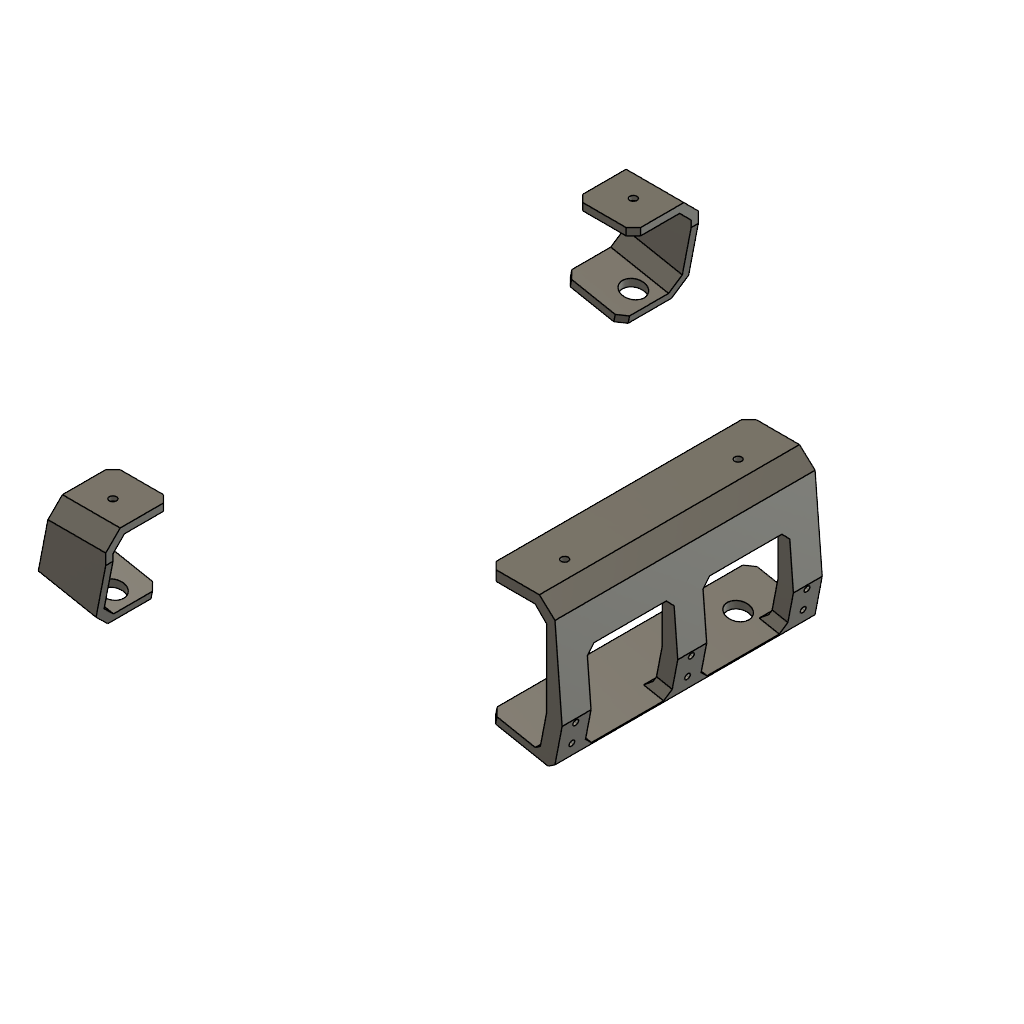
LaptopDeskMountMk2 (Autodesk Fusion 360 design; units mm, degrees)
part number: 2026-11-20-12-05-45-084
Autodesk Fusion 360 part; units mm, degrees
sketch "Sketch1" plane through (0, 0, 0) normal (0, 0, 1) x (1, 0, 0)
  line L0 (0, 0) -> (280, 0)
  line L1 (280, 0) -> (280, -127.8735)
  line L2 (0, 0) -> (280, -54.4265)
  line L3 (0, 0) -> (285.2407, 0) construction
  line L4 (0, 0) -> (50, 0)
  line L5 (50, 0) -> (90, 0)
  line L6 (50, 0) -> (50, -9.719)
  line L7 (90, 0) -> (90, -17.4942)
  line L8 (90, -17.4942) -> (82.3676, -56.7593)
  line L9 (50, -9.719) -> (42.3676, -48.9841)
  line L10 (42.3676, -48.9841) -> (82.3676, -56.7593)
  dimension "d1" = 280
  dimension "d2" = 11
  dimension "d3" = 50
  dimension "d4" = 40
  dimension "d5" = 40
  dimension "d6" = 40
  constraint coincident L0.start L2.start
  constraint horizontal L0
  constraint perpendicular L0 L1
  constraint horizontal L3
  constraint coincident L1 L2.end
  constraint parallel L3 L4
  constraint parallel L3 L5
  constraint coincident L2 L6.end
  constraint perpendicular L4 L6
  constraint coincident L2 L7.end
  constraint perpendicular L0 L7
  constraint perpendicular L2 L8
  constraint perpendicular L2 L9
  measures "d1" distance of L0.start L0.end
  measures "d2" angle of L2 L3
  measures "d3" distance of L0.start L4.end
  measures "d4" distance of L4.end L5.end
  measures "d5" distance of L7.end L8.end
  measures "d6" distance of L6.end L9.end
extrude "Extrude1" add sketch "Sketch1" along normal blind 5 contours L0 L2 L5 L6 L7 | L2 L8 L9 L10 makes body 1
sketch "Sketch2" plane through (0, 0, 0) normal (0, 1, 0) x (-1, 0, 0)
  line L0 (-90, 0) -> (-50, 0)
  line L1 (-50, 0) -> (-50, 5)
  line L2 (-50, 5) -> (-90, 5)
  line L3 (-90, 5) -> (-90, 0)
  line L4 (-90, 5) -> (-90, 45)
  line L5 (-90, 45) -> (-50, 45)
  line L6 (-50, 45) -> (-50, 5)
  line L7 (-50, 5) -> (-90, 5)
  line L8 (-90, 5) -> (-90, 45)
  line L9 (-90, 25) -> (-50, 25)
  circle A0 centre (-70, 25) radius 2.5
  dimension "d9" = 40
  dimension "d10" = 5
  constraint coincident L2.end L3.start
  constraint perpendicular L2 L4
  constraint horizontal L5
  constraint vertical L6
  constraint horizontal L7
  constraint vertical L8
  constraint coincident L1.end L2.start
  constraint midpoint L8 L9.start
  constraint midpoint L6 L9.end
  constraint midpoint L9 A0.centre
  measures "d9" distance of L2.end L4.end
  measures "d10" diameter of A0
extrude "Extrude2" add sketch "Sketch2" against normal blind 5 contours L2 L4 L6 L7 L8 L9 A0 | L4 L5 L6 L8 L9 A0 bodies 1
sketch "Sketch3" plane through (-7.6324, -39.2651, 0) normal (-0.190809, -0.981627, 0) x (0, 0, 1)
  line L0 (0, -50.9358) -> (0, -91.6845)
  line L1 (0, -91.6845) -> (5, -91.6845)
  line L2 (5, -91.6845) -> (5, -50.9358)
  line L3 (5, -50.9358) -> (0, -50.9358)
  line L4 (5, -50.9358) -> (45, -50.9358)
  line L5 (45, -50.9358) -> (5, -50.9358)
  line L6 (5, -50.9358) -> (5, -91.6845)
  line L7 (5, -91.6845) -> (45, -91.6845)
  line L8 (45, -91.6845) -> (45, -50.9358)
  dimension "d13" = 40
  constraint coincident L2.end L3.start
  constraint perpendicular L2 L4
  constraint horizontal L5
  constraint vertical L6
  constraint horizontal L7
  constraint vertical L8
  constraint coincident L1.end L2.start
  measures "d13" distance of L2.end L4.end
extrude "Extrude3" add sketch "Sketch3" along normal blind 5 bodies 1
sketch "Sketch4" plane through (0, -5, 0) normal (0, -1, 0) x (1, 0, 0)
  circle A0 centre (70, 25) radius 2.5
  line L0 (50, 5) -> (90, 5)
  line L1 (90, 5) -> (90, 45)
  line L2 (90, 45) -> (50, 45)
  line L3 (50, 45) -> (50, 5)
  circle A1 centre (70, 25) radius 7.5
  dimension "d16" = 15
  constraint concentric A0 A1
  measures "d16" diameter of A1
extrude "Extrude4" cut sketch "Sketch4" along normal blind 60 contours A0 | A1 bodies 1
hole "Hole1" at (70, -5, 25) direction (0, 1, 0) diameter 8 depth 1 tip angle 118 bodies 1
chamfer "Chamfer2" distance 8 angle 45 2 edges at (70, -5, 5) (62.3676, -52.8717, 5) tangent chain off on bodies 1
chamfer "Chamfer3" distance 10 angle 45 2 edges at (70, 0, 0) (61.4136, -57.7798, 0) tangent chain off on bodies 1
chamfer "Chamfer4" distance 5 angle 45 4 edges at (50, -2.5, 45) (90, -2.5, 45) (41.8906, -51.4382, 45) (81.8906, -59.2134, 45) tangent chain off on bodies 1
sketch "Sketch5" plane through (0, 0, 0) normal (0, 0, 1) x (1, 0, 0)
  line L0 (0, 0) -> (280, 0)
  line L1 (280, 0) -> (280, -128)
  line L2 (0, 0) -> (280, -54.4265)
  line L3 (0, 0) -> (285.2407, 0) construction
  line L4 (280, 0) -> (240, 0)
  line L5 (280, 0) -> (285, 0)
  line L6 (280, -54.4265) -> (280, -94.4265)
  line L7 (280, -94.4265) -> (240.7349, -86.7941)
  line L8 (280, -94.4265) -> (320, -94.4265) construction
  line L9 (240.7349, -86.7941) -> (239.7809, -91.7023)
  line L10 (239.7809, -91.7023) -> (285, -100.492)
  line L11 (285, -100.492) -> (285, 0)
  line L12 (240, 0) -> (240, -7)
  line L13 (240, -7) -> (280, -7)
  dimension "d19" = 280
  dimension "d20" = 128
  dimension "d21" = 11
  dimension "d22" = 40
  dimension "d23" = 5
  dimension "d24" = 40
  dimension "d25" = 169
  dimension "d26" = 40
  dimension "d27" = 5
  dimension "d28" = 7
  constraint coincident L0.start L2.start
  constraint horizontal L0
  constraint perpendicular L0 L1
  constraint horizontal L3
  constraint coincident L1 L2.end
  constraint perpendicular L1 L4
  constraint perpendicular L1 L5
  constraint parallel L1 L6
  constraint horizontal L8
  constraint perpendicular L7 L9
  constraint perpendicular L9 L10
  constraint perpendicular L5 L11
  constraint perpendicular L0 L12
  constraint coincident L1 L13.end
  constraint perpendicular L1 L13
  measures "d19" distance of L0.start L0.end
  measures "d20" distance of L0.end L1.end
  measures "d21" angle of L2 L3
  measures "d22" distance of L0.end L4.end
  measures "d23" distance of L0.end L5.end
  measures "d24" distance of L2.end L6.end
  measures "d25" angle of L7 L8
  measures "d26" distance of L6.end L7.end
  measures "d27" distance of L7.end L9.end
  measures "d28" distance of L4.end L12.end
extrude "Extrude5" add sketch "Sketch5" along normal blind 180 separate body contours L0 L1 L4 L12 L13 | L1 L5 L6 L10 L11 | L1 L7 L9 L10 makes body 2
sketch "Sketch7" plane through (0, 0, 180) normal (0, 0, 1) x (1, 0, 0)
  line L0 (285, 0) -> (240, 0)
  line L1 (240, 0) -> (240, -7)
  line L2 (240, -7) -> (280, -7)
  line L3 (280, -7) -> (280, -94.4265)
  line L4 (280, -94.4265) -> (240.7349, -86.7941)
  line L5 (240.7349, -86.7941) -> (239.7809, -91.7023)
  line L6 (239.7809, -91.7023) -> (285, -100.492)
  line L7 (285, -100.492) -> (285, 0)
  line L8 (280, -94.4265) -> (275.0919, -93.4724)
  line L9 (275.0919, -93.4724) -> (280, -68.2223)
  line L10 (285, -100.492) -> (290.7243, -71.0432)
  line L11 (290.7243, -71.0432) -> (285, 0)
  dimension "d39" = 5
  dimension "d86" = 30
  constraint coincident L3.end L4.start
  constraint parallel L4 L8
  constraint coincident L3 L9.end
  constraint perpendicular L8 L9
  constraint coincident L6.end L7.start
  constraint perpendicular L6 L10
  constraint coincident L0.start L7.end
  measures "d39" distance of L3.end L8.end
  measures "d86" distance of L6.end L10.end
extrude "Extrude8" add sketch "Sketch7" against normal blind 180 contours L7 L10 L11 | L3 L4 L8 L9 bodies 2
sketch "Sketch6" plane through (248.227, -48.2504, 0) normal (-0.981627, 0.190809, 0) x (0, 0, 1)
  line L0 (0, -39.2651) -> (0, -44.2651)
  line L1 (0, -44.2651) -> (180, -44.2651)
  line L2 (180, -44.2651) -> (180, -39.2651)
  line L3 (180, -39.2651) -> (0, -39.2651)
  line L4 (180, -39.2651) -> (160, -39.2651)
  line L5 (0, -39.2651) -> (20, -39.2651)
  line L6 (20, -39.2651) -> (80, -39.2651)
  line L7 (160, -39.2651) -> (100, -39.2651)
  line L8 (100, -39.2651) -> (80, -39.2651)
  line L9 (100, -39.2651) -> (100, 20.7349)
  line L10 (100, 20.7349) -> (160, 20.7349)
  line L11 (160, 20.7349) -> (160, -39.2651)
  line L12 (160, -39.2651) -> (100, -39.2651)
  line L13 (100, -39.2651) -> (100, 20.7349)
  line L14 (80, -39.2651) -> (80, 20.7349)
  line L15 (80, 20.7349) -> (20, 20.7349)
  line L16 (20, 20.7349) -> (20, -39.2651)
  line L17 (20, -39.2651) -> (80, -39.2651)
  line L18 (80, -39.2651) -> (80, 20.7349)
  dimension "d31" = 20
  dimension "d32" = 20
  dimension "d33" = 60
  dimension "d34" = 60
  dimension "d35" = 60
  dimension "d36" = 60
  constraint coincident L2.end L3.start
  constraint perpendicular L2 L4
  constraint coincident L0.start L3.end
  constraint perpendicular L0 L5
  constraint parallel L3 L6
  constraint parallel L3 L7
  constraint perpendicular L3 L9
  constraint horizontal L10
  constraint vertical L11
  constraint horizontal L12
  constraint vertical L13
  constraint perpendicular L3 L14
  constraint horizontal L15
  constraint vertical L16
  constraint horizontal L17
  constraint vertical L18
  measures "d31" distance of L2.end L4.end
  measures "d32" distance of L0.start L5.end
  measures "d33" distance of L5.end L6.end
  measures "d34" distance of L4.end L7.end
  measures "d35" distance of L7.end L9.end
  measures "d36" distance of L6.end L14.end
extrude "Extrude6" cut sketch "Sketch6" against normal blind 50 contours L3 L6 L14 L15 L16 L17 L18 | L3 L7 L9 L10 L11 L12 L13 bodies 2
sketch "Sketch8" plane through (0, 0, 0) normal (0, 1, 0) x (-1, 0, 0)
  line L0 (-285, 0) -> (-240, 0)
  line L1 (-240, 0) -> (-240, 180)
  line L2 (-240, 180) -> (-285, 180)
  line L3 (-262.5, 0) -> (-262.5, 30)
  line L4 (-262.5, 180) -> (-262.5, 150)
  circle A0 centre (-262.5, 150) radius 2.5
  circle A1 centre (-262.5, 30) radius 2.5
  line L5 (-285, 180) -> (-285, 0)
  dimension "d44" = 30
  dimension "d45" = 30
  dimension "d46" = 5
  dimension "d47" = 5
  constraint midpoint L0 L3.start
  constraint perpendicular L0 L3
  constraint midpoint L2 L4.start
  constraint perpendicular L2 L4
  constraint coincident L4.end A0.centre
  constraint coincident L3.end A1.centre
  measures "d44" distance of L3.start L3.end
  measures "d45" distance of L4.start L4.end
  measures "d46" diameter of A0
  measures "d47" diameter of A1
extrude "Extrude9" cut sketch "Sketch8" against normal blind 100 contours A0 | A1 bodies 2
sketch "Sketch9" plane through (0, -7, 0) normal (0, -1, 0) x (1, 0, 0)
  circle A0 centre (262.5, 30) radius 2.5
  circle A1 centre (262.5, 150) radius 2.5
  line L0 (240, 0) -> (280, 0)
  line L1 (280, 0) -> (280, 180)
  line L2 (280, 180) -> (240, 180)
  line L3 (240, 180) -> (240, 0)
  circle A2 centre (262.5, 150) radius 7.5
  circle A3 centre (262.5, 30) radius 7.5
  dimension "d53" = 15
  dimension "d54" = 15
  constraint concentric A1 A2
  constraint concentric A0 A3
  measures "d53" diameter of A2
  measures "d54" diameter of A3
extrude "Extrude10" cut sketch "Sketch9" along normal blind 100 contours A0 | A1 | A2 | A3 bodies 2
hole "Hole2" at (262.5, -7, 30) direction (0, 1, 0) diameter 8 depth 1 tip angle 118 bodies 2
hole "Hole3" at (262.5, -7, 150) direction (0, 1, 0) diameter 8 depth 1 tip angle 118 bodies 2
sketch "Sketch10" plane through (248.227, -48.2504, 0) normal (-0.981627, 0.190809, 0) x (0, 0, 1)
  line L0 (0, -39.2651) -> (0, -44.2651)
  line L1 (0, -44.2651) -> (180, -44.2651)
  line L2 (180, -44.2651) -> (180, -39.2651)
  line L3 (180, -39.2651) -> (0, -39.2651)
  line L4 (0, -39.2651) -> (10, -39.2651)
  line L5 (10, -39.2651) -> (10, -17.2651)
  line L6 (90, -39.2651) -> (90, -17.2651)
  line L7 (10, -39.2651) -> (10, -31.2651)
  line L8 (90, -39.2651) -> (90, -31.2651)
  line L9 (180, -39.2651) -> (170, -39.2651)
  line L10 (170, -39.2651) -> (170, -31.2651)
  line L11 (170, -39.2651) -> (170, -17.2651)
  circle A0 centre (170, -17.2651) radius 2
  circle A1 centre (170, -31.2651) radius 2
  circle A2 centre (90, -17.2651) radius 2
  circle A3 centre (90, -31.2651) radius 2
  circle A4 centre (10, -17.2651) radius 2
  circle A5 centre (10, -31.2651) radius 2
  dimension "d70" = 10
  dimension "d71" = 22
  dimension "d72" = 22
  dimension "d73" = 8
  dimension "d74" = 8
  dimension "d75" = 10
  dimension "d76" = 8
  dimension "d77" = 22
  dimension "d78" = 4
  dimension "d79" = 4
  dimension "d80" = 4
  dimension "d81" = 4
  dimension "d82" = 4
  dimension "d83" = 4
  constraint coincident L0.start L3.end
  constraint perpendicular L0 L4
  constraint perpendicular L4 L5
  constraint midpoint L3 L6.start
  constraint perpendicular L3 L6
  constraint perpendicular L4 L7
  constraint perpendicular L3 L8
  constraint coincident L2.end L3.start
  constraint perpendicular L2 L9
  constraint perpendicular L3 L10
  constraint perpendicular L3 L11
  constraint coincident L11.end A0.centre
  constraint coincident L10.end A1.centre
  constraint coincident L6.end A2.centre
  constraint coincident L8.end A3.centre
  constraint coincident L5.end A4.centre
  constraint coincident L7.end A5.centre
  measures "d70" distance of L0.start L4.end
  measures "d71" distance of L4.end L5.end
  measures "d72" distance of L6.start L6.end
  measures "d73" distance of L4.end L7.end
  measures "d74" distance of L6.start L8.end
  measures "d75" distance of L2.end L9.end
  measures "d76" distance of L9.end L10.end
  measures "d77" distance of L9.end L11.end
  measures "d78" diameter of A0
  measures "d79" diameter of A1
  measures "d80" diameter of A2
  measures "d81" diameter of A3
  measures "d82" diameter of A4
  measures "d83" diameter of A5
extrude "Extrude11" cut sketch "Sketch10" against normal blind 50 contours L5 L7 A5 | L5 L7 A5 | L6 L8 A3 | L6 L8 A3 | L10 L11 A1 | L10 L11 A1 | A0 | A2 | A4 bodies 2
chamfer "Chamfer1" distance 8 angle 45 1 edges at (280, -7, 90) tangent chain off on bodies 2
chamfer "Chamfer5" distance 10 angle 45 1 edges at (285, 0, 90) tangent chain off on bodies 2
chamfer "Chamfer6" distance 4 angle 45 1 edges at (285, -100.492, 90) tangent chain off on bodies 2
chamfer "Chamfer7" distance 5 angle 45 4 edges at (240, -3.5, 0) (240, -3.5, 180) (240.2579, -89.2482, 180) (240.2579, -89.2482, 0) tangent chain off on bodies 2
chamfer "Chamfer8" distance 5 angle 45 8 edges at (280.523, -94.5281, 20) (280.523, -94.5281, 80) (280.523, -94.5281, 160) (280.523, -94.5281, 100) (283.9028, -34.0621, 100) (283.9028, -34.0621, 20) (283.9028, -34.0621, 80) (283.9028, -34.0621, 160) tangent chain off on bodies 2
chamfer "Chamfer9" distance 3 angle 45 3 edges at (275.0919, -93.4724, 12.5) (275.0919, -93.4724, 90) (275.0919, -93.4724, 167.5) tangent chain off on bodies 2
hole "Hole4" at (279.2897, -71.8766, 90) direction (0.981627, -0.190809, 0) diameter 7 depth 1 tip angle 118 bodies 2
hole "Hole5" at (276.6183, -85.6194, 90) direction (0.981627, -0.190809, 0) diameter 7 depth 1 tip angle 118 bodies 2
hole "Hole6" at (279.2897, -71.8766, 10) direction (0.981627, -0.190809, 0) diameter 7 depth 1 tip angle 118 bodies 2
hole "Hole7" at (276.6183, -85.6194, 10) direction (0.981627, -0.190809, 0) diameter 7 depth 1 tip angle 118 bodies 2
hole "Hole8" at (279.2897, -71.8766, 170) direction (0.981627, -0.190809, 0) diameter 7 depth 1 tip angle 118 bodies 2
hole "Hole9" at (276.6183, -85.6194, 170) direction (0.981627, -0.190809, 0) diameter 7 depth 1 tip angle 118 bodies 2
sketch "Sketch11" plane through (-7.4921, -38.5437, 0) normal (0.190809, 0.981627, 0) x (0, 0, -1)
  ellipse E0 centre (-30, -275.0455) end of major axis (-30, -282.6859) minor radius 7.5
  ellipse E1 centre (-150, -275.0455) end of major axis (-150, -282.6859) minor radius 7.5
  line L0 (-180, -284.873) -> (-155, -284.873)
  line L1 (-155, -284.873) -> (-155, -298.9385)
  line L2 (-155, -298.9385) -> (-105, -298.9385)
  line L3 (-105, -298.9385) -> (-105, -284.873)
  line L4 (-105, -284.873) -> (-75, -284.873)
  line L5 (-75, -284.873) -> (-75, -298.9385)
  line L6 (-75, -298.9385) -> (-25, -298.9385)
  line L7 (-25, -298.9385) -> (-25, -284.873)
  line L8 (-25, -284.873) -> (0, -284.873)
  line L9 (0, -284.873) -> (0, -257.873)
  line L10 (0, -257.873) -> (-5, -252.873)
  line L11 (-5, -252.873) -> (-175, -252.873)
  line L12 (-175, -252.873) -> (-180, -257.873)
  line L13 (-180, -257.873) -> (-180, -284.873)
  line L14 (-90, -284.873) -> (100, -284.873)
  line L15 (100, -284.873) -> (100, -24.873)
  line L16 (-90, -284.873) -> (-280, -284.873)
  line L17 (-280, -284.873) -> (-280, -24.873)
  dimension "d107" = 190
  dimension "d108" = 260
  dimension "d109" = 190
  dimension "d110" = 260
  dimension "d109" = 190
  constraint midpoint L4 L14.start
  constraint parallel L4 L14
  constraint perpendicular L14 L15
  constraint perpendicular L5 L16
  constraint perpendicular L16 L17
  measures "d107" distance of L14.start L14.end
  measures "d108" distance of L14.end L15.end
  measures "d109" distance of L14.start L16.end
  measures "d110" distance of L16.end L17.end
move_body "Move1" bodies 1 to x (1, 0, 0) y (0, 1, 0) z (0, 0, 1) at (0, 0, -115)
ref_plane "WorkPlane1" through (267.7066, -49.8644, 90) normal (0, 0, 1) x (1, 0, 0)
mirror "Mirror1" about plane through (267.7066, -49.8644, 90) normal (0, 0, 1) of bodies 1 makes body 3
equation "d25 = 180 deg - 11 deg"
equation "d107 = ( 380 / 2 ) * 1 mm"
equation "d109 = ( 380 / 2 ) * 1 mm"
equation "d109 = ( 380 / 2 ) * 1 mm"
named bodies: "LaptopDeskMountMk2_Side", "LaptopDeskMountMk2_Back", "LaptopDeskMountMk2_Side (1)"
